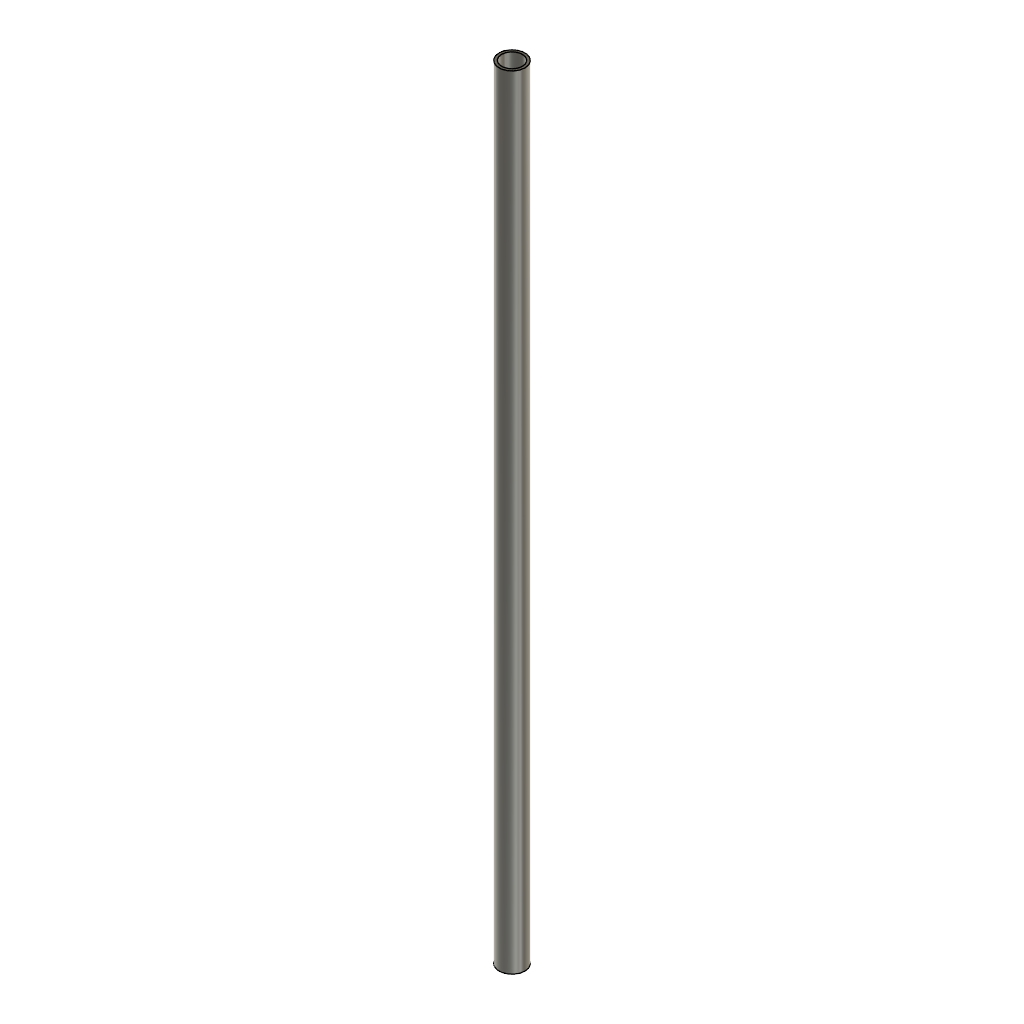
Robot_Umbrella_v2 (Autodesk Fusion 360 archive; units mm, degrees)
design "Rib_01"
part number: 2026-10-13-21-00-24-869
Autodesk Fusion 360 part; units mm, degrees
sketch "스케치5" plane through (0, 0, 0) normal (0, 0, 1) x (1, 0, 0)
  circle A0 centre (0, 0) radius 5
  circle A1 centre (0, 0) radius 4
  dimension "d5" = 10
  dimension "d6" = 8
  constraint coincident A0.centre A1.centre
  constraint concentric A0 A1
  measures "d5" diameter of A0
  measures "d6" diameter of A1
extrude "돌출1" add sketch "스케치5" along normal blind 300
equation "Rib_OD = 10 mm" comment "카본 리브 외경"
equation "Rib_ID = 8 mm" comment "카본 리브 내경"
equation "Rib_Length = 300 mm" comment "리브 길이 (임시 설계값)"
equation "d5 = Rib_OD"
equation "d6 = Rib_ID"
equation "d7 = Rib_Length"

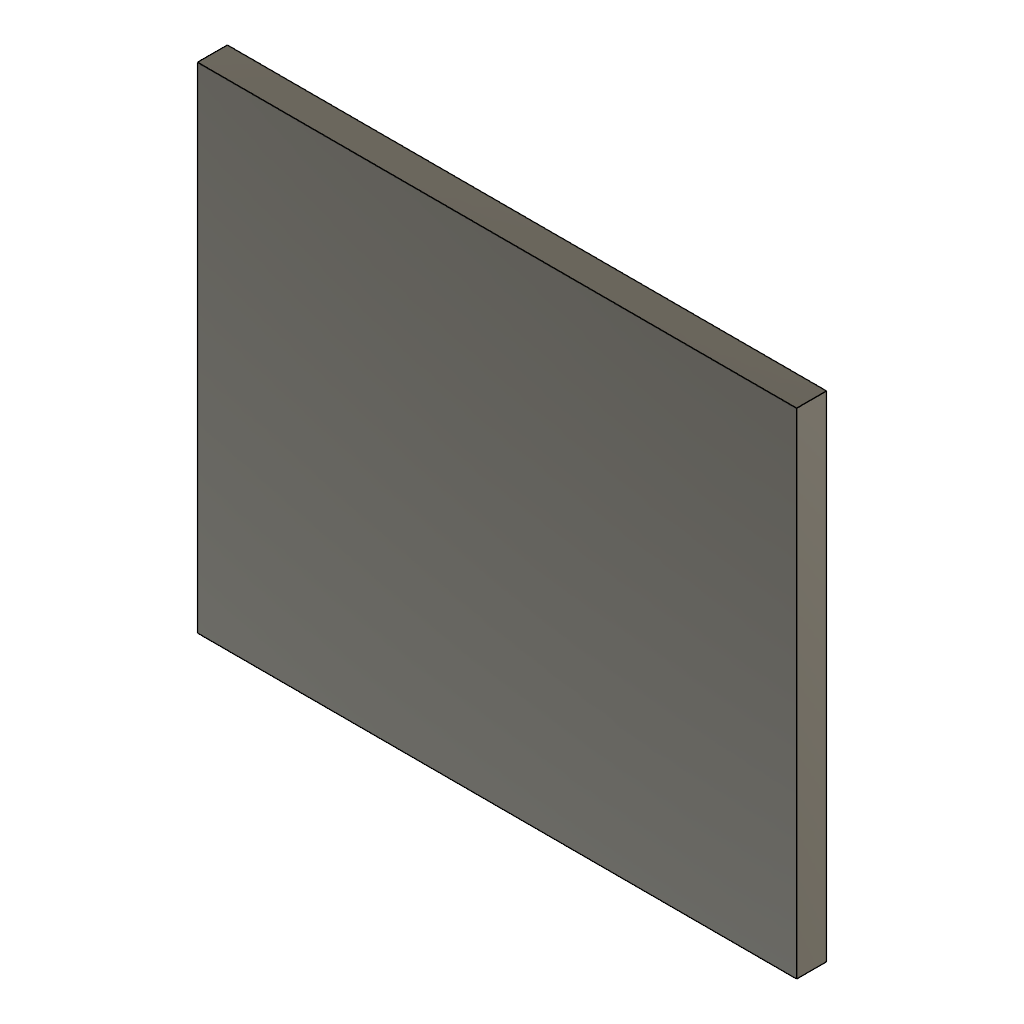
design "Base_Bracket"
part number: 2026-10-13-21-20-43-710
Autodesk Fusion 360 part; units mm, degrees
sketch "스케치1" plane through (0, 0, 0) normal (0, 0, 1) x (1, 0, 0)
  line L0 (0, 0) -> (40, 0)
  line L1 (40, 0) -> (40, 40)
  line L2 (40, 40) -> (0, 40)
  line L3 (0, 40) -> (0, 0)
  dimension "d1" = 40
  dimension "d2" = 40
  constraint horizontal L0
  constraint vertical L1
  constraint horizontal L2
  constraint vertical L3
  constraint coincident L0.start L3.end
  measures "d1" distance of L0.start L0.end
  measures "d2" distance of L0.start L2.end
extrude "돌출1" add sketch "스케치1" along normal blind 330
extrude "돌출2" add 1 faces at (40, 13.3333, 110) along direction (1, 0, 0) blind 360
extrude "돌출3" cut 1 faces at (133.3333, 0, 110) along direction (0, 1, 0) blind 20
sketch "스케치2" plane through (0, 0, 0) normal (0, 1, 0) x (1, 0, 0)

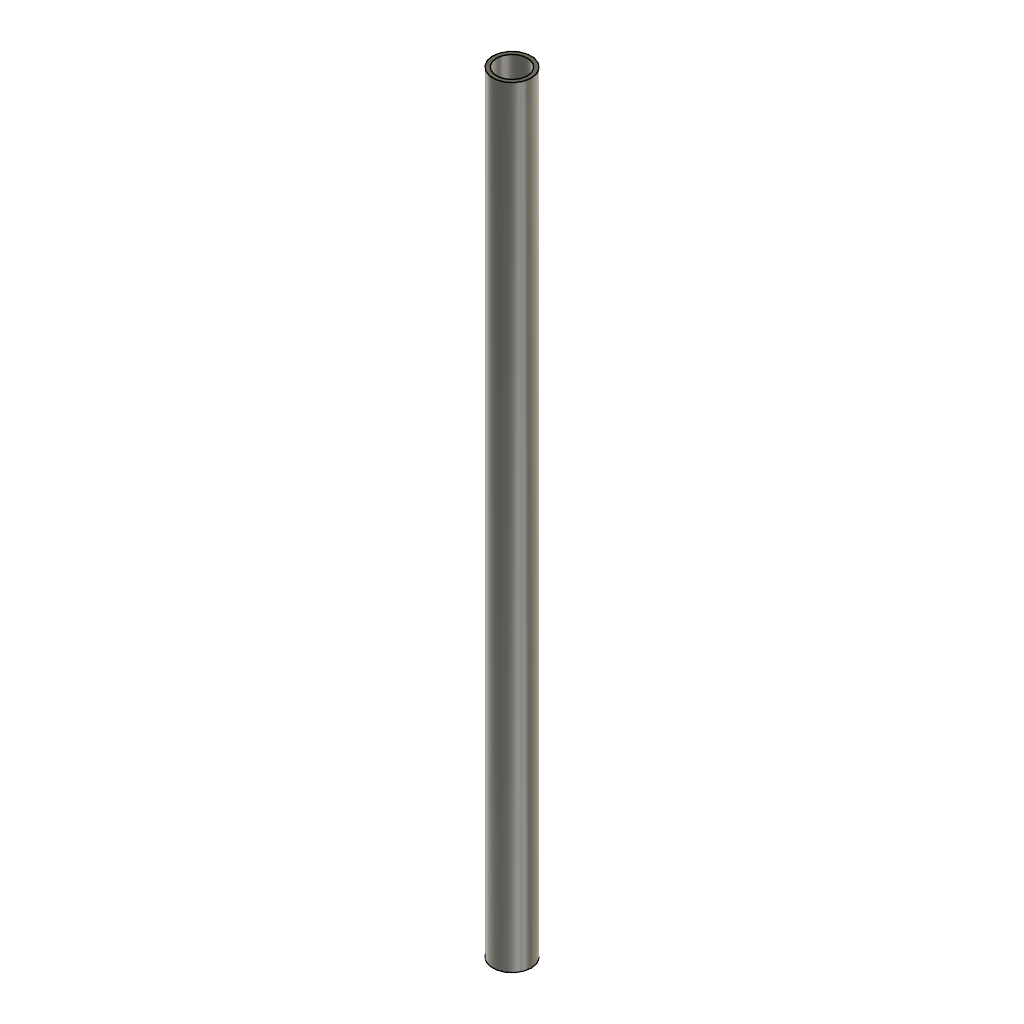
design "Rib_02"
part number: 2026-10-14-01-21-34-500
Autodesk Fusion 360 part; units mm, degrees
sketch "스케치1" plane through (0, 0, 0) normal (0, 0, 1) x (1, 0, 0)
  circle A0 centre (0, 0) radius 5
  circle A1 centre (0, 0) radius 4
  dimension "d1" = 10
  dimension "d2" = 8
  constraint coincident A0.centre A1.centre
  measures "d1" diameter of A0
  measures "d2" diameter of A1
extrude "돌출1" add sketch "스케치1" along normal blind 200

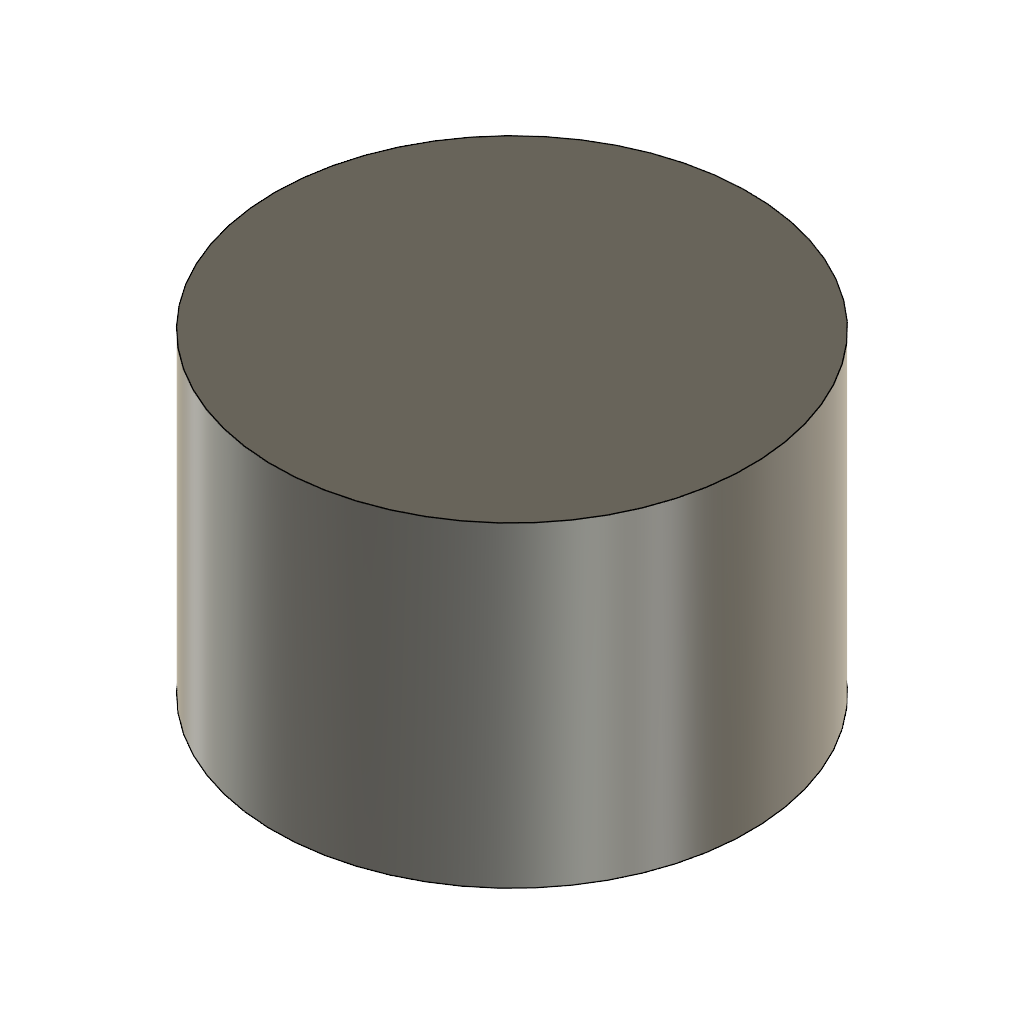
design "Joint_02"
part number: 2026-10-14-01-13-29-471
Autodesk Fusion 360 part; units mm, degrees
sketch "스케치1" plane through (0, 0, 0) normal (0, 0, 1) x (1, 0, 0)
  circle A0 centre (0, 0) radius 15
  dimension "d1" = 30
  constraint coincident A0.centre origin
  measures "d1" diameter of A0
extrude "돌출1" add sketch "스케치1" along normal blind 20

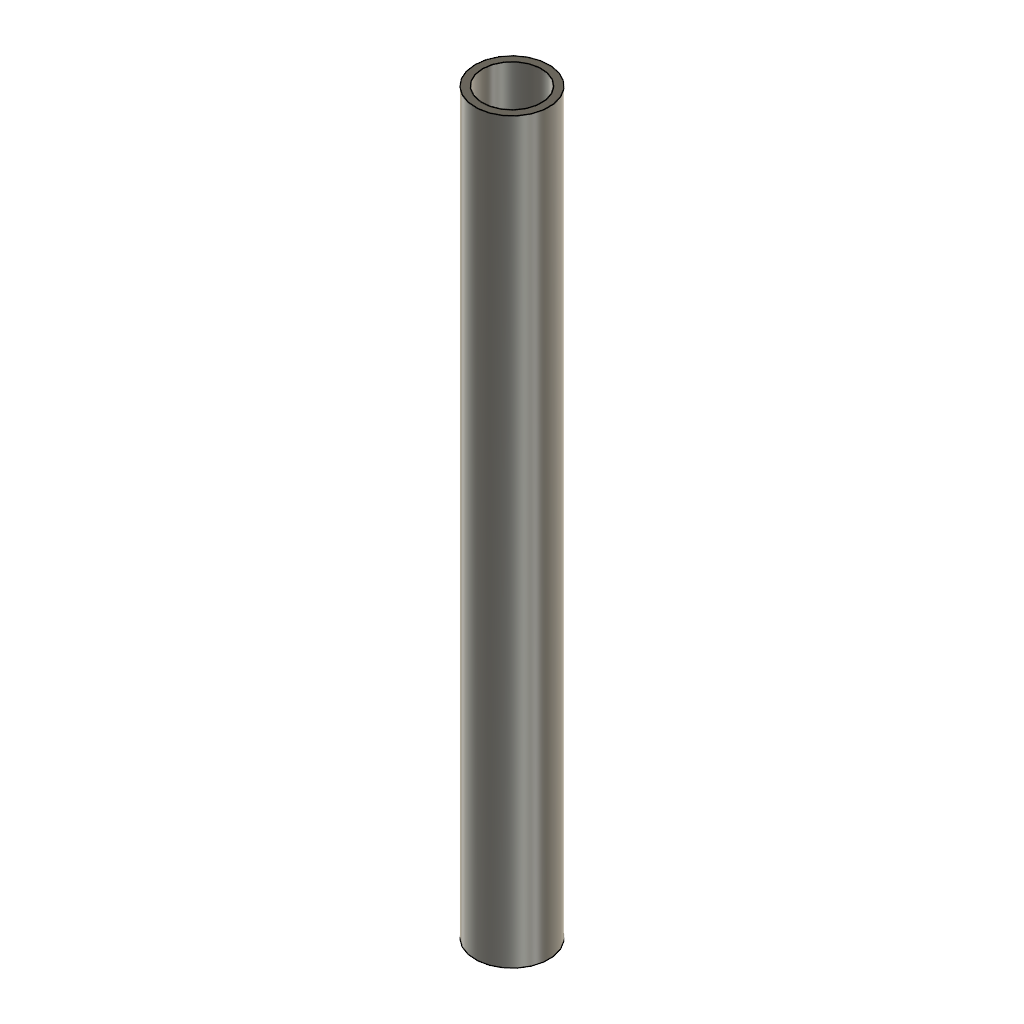
design "Rib_03"
part number: 2026-10-14-03-14-08-121
Autodesk Fusion 360 part; units mm, degrees
sketch "스케치1" plane through (0, 0, 0) normal (0, 0, 1) x (1, 0, 0)
  circle A0 centre (0, 0) radius 5
  circle A1 centre (0, 0) radius 4
  dimension "d1" = 10
  dimension "d2" = 8
  constraint coincident A0.centre A1.centre
  constraint concentric A0 A1
  measures "d1" diameter of A0
  measures "d2" diameter of A1
extrude "돌출1" add sketch "스케치1" along normal blind 100

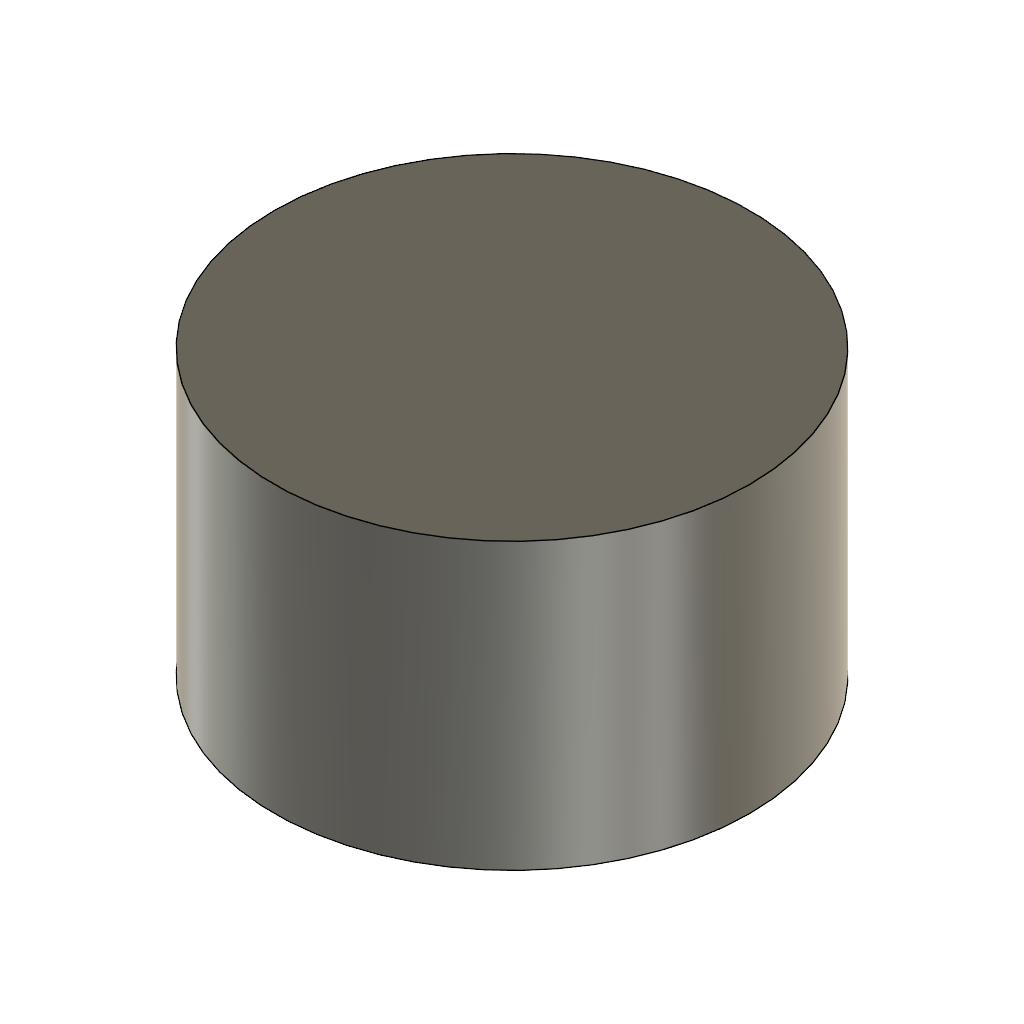
design "Joint_01"
part number: 2026-10-13-22-44-03-240
Autodesk Fusion 360 part; units mm, degrees
sketch "스케치1" plane through (0, 0, 0) normal (0, 0, 1) x (1, 0, 0)
  circle A0 centre (0, 0) radius 12.5
  dimension "d1" = 25
  constraint coincident A0.centre origin
  measures "d1" diameter of A0
extrude "돌출1" add sketch "스케치1" along normal blind 15
